left_case_fastening_v03_NOT_FOR_MANUFACTURE (Autodesk Fusion 360 design; units mm, degrees)
part number: 2026-11-07-02-20-21-225
part number: 2026-11-07-02-20-21-469
part number: 2026-11-07-02-20-24-646
part number: 2026-11-07-02-20-27-170
part number: 2026-11-07-02-26-06-783
Autodesk Fusion 360 part; units mm, degrees
sketch "スケッチ1" plane through (0, 0, 0) normal (0, 0, 1) x (1, 0, 0) in component "Lower_L_FROM_PCB_OUTLINE_PROVISIONAL"
  line L0 (-49.47, 7.054) -> (-65.52, 7.054) construction
  arc A0 (-65.52, 7.054) -> (-66.52, 6.054) centre (-65.52, 6.054) ccw construction
  line L1 (-66.52, 6.054) -> (-66.52, 3.354) construction
  arc A1 (-67.52, 2.354) -> (-66.52, 3.354) centre (-67.52, 3.354) ccw construction
  line L2 (-67.52, 2.354) -> (-84.57, 2.354) construction
  arc A2 (-84.57, 2.354) -> (-85.57, 1.354) centre (-84.57, 1.354) ccw construction
  line L3 (-85.57, 1.354) -> (-85.57, -3.646) construction
  arc A3 (-86.57, -4.646) -> (-85.57, -3.646) centre (-86.57, -3.646) ccw construction
  line L4 (-86.57, -4.646) -> (-103.62, -4.646) construction
  arc A4 (-103.62, -4.646) -> (-104.62, -5.646) centre (-103.6199, -5.6461) ccw construction
  line L5 (-104.62, -5.646) -> (-104.62, -78.846) construction
  arc A5 (-104.62, -78.846) -> (-103.62, -79.846) centre (-103.62, -78.846) ccw construction
  line L6 (-103.62, -79.846) -> (-87.57, -79.846) construction
  arc A6 (-87.57, -79.846) -> (-86.57, -78.846) centre (-87.57, -78.846) ccw construction
  line L7 (-86.57, -78.846) -> (-86.57, -73.846) construction
  arc A7 (-85.57, -72.846) -> (-86.57, -73.846) centre (-85.57, -73.846) ccw construction
  line L8 (-85.57, -72.846) -> (-68.52, -72.846) construction
  arc A8 (-68.52, -72.846) -> (-67.52, -71.846) centre (-68.52, -71.846) ccw construction
  line L9 (-67.52, -71.846) -> (-67.52, -69.146) construction
  arc A9 (-66.52, -68.146) -> (-67.52, -69.146) centre (-66.52, -69.146) ccw construction
  line L10 (-66.52, -68.146) -> (-49.47, -68.146) construction
  arc A10 (-49.47, -68.146) -> (-48.47, -67.146) centre (-49.47, -67.146) ccw construction
  line L11 (-48.47, -67.146) -> (-48.47, -55.096) construction
  arc A11 (-47.47, -54.096) -> (-48.47, -55.096) centre (-47.47, -55.096) ccw construction
  line L12 (-47.47, -54.096) -> (-44.47, -54.096) construction
  arc A12 (-43.47, -55.096) -> (-44.47, -54.096) centre (-44.47, -55.096) ccw construction
  line L13 (-43.47, -55.096) -> (-43.47, -76.846) construction
  arc A13 (-43.47, -76.846) -> (-42.47, -77.846) centre (-42.47, -76.846) ccw construction
  line L14 (-42.47, -77.846) -> (-25.5816, -77.846) construction
  arc A14 (-25.2605, -77.8719) -> (-25.5816, -77.846) centre (-25.5815, -79.8459) ccw construction
  line L15 (-25.2605, -77.8719) -> (-5.7378, -81.0467) construction
  arc A15 (-5.3997, -81.1324) -> (-5.7378, -81.0467) centre (-6.0588, -83.0207) ccw construction
  line L16 (-5.3997, -81.1324) -> (12.4958, -87.3783) construction
  arc A16 (12.4958, -87.3783) -> (13.765, -86.7762) centre (12.8253, -86.4342) ccw construction
  line L17 (13.765, -86.7762) -> (19.2592, -71.6805) construction
  arc A17 (19.2592, -71.6805) -> (18.6615, -70.3988) centre (18.3195, -71.3385) ccw construction
  line L18 (18.6615, -70.3988) -> (10.7342, -67.5136) construction
  arc A18 (10.0762, -66.5739) -> (10.7342, -67.5136) centre (11.0762, -66.5739) ccw construction
  line L19 (10.0762, -66.5739) -> (10.0762, -1.946) construction
  line L20 (10.0762, -1.946) -> (10.0762, -0.946) construction
  arc A19 (10.0762, -0.946) -> (9.0762, 0.054) centre (9.0762, -0.946) ccw construction
  line L21 (9.0762, 0.054) -> (-9.37, 0.054) construction
  arc A20 (-10.37, 1.054) -> (-9.37, 0.054) centre (-9.37, 1.054) ccw construction
  arc A21 (-10.37, 1.054) -> (-11.37, 2.054) centre (-11.37, 1.054) ccw construction
  line L22 (-11.37, 2.054) -> (-28.42, 2.054) construction
  arc A22 (-29.42, 3.054) -> (-28.42, 2.054) centre (-28.42, 3.054) ccw construction
  line L23 (-29.42, 3.054) -> (-29.42, 3.554) construction
  arc A23 (-29.42, 3.554) -> (-30.42, 4.554) centre (-30.42, 3.554) ccw construction
  line L24 (-30.42, 4.554) -> (-47.47, 4.554) construction
  arc A24 (-48.47, 5.554) -> (-47.47, 4.554) centre (-47.47, 5.554) ccw construction
  line L25 (-48.47, 5.554) -> (-48.47, 6.054) construction
  arc A25 (-48.47, 6.054) -> (-49.47, 7.054) centre (-49.47, 6.054) ccw construction
  line L26 (-49.47, 11.054) -> (-65.52, 11.054)
  arc A26 (-65.52, 11.054) -> (-70.511, 6.354) centre (-65.52, 6.054) ccw
  line L27 (-70.511, 6.354) -> (-84.57, 6.354)
  arc A27 (-84.57, 6.354) -> (-89.57, 1.354) centre (-84.57, 1.354) ccw
  line L28 (-89.57, 1.354) -> (-89.57, -0.646)
  line L29 (-89.57, -0.646) -> (-103.6201, -0.646)
  arc A28 (-103.6201, -0.646) -> (-108.62, -5.6459) centre (-103.6199, -5.6461) ccw
  line L30 (-108.62, -5.6459) -> (-108.62, -78.846)
  arc A29 (-108.62, -78.846) -> (-103.62, -83.846) centre (-103.62, -78.846) ccw
  line L31 (-103.62, -83.846) -> (-87.57, -83.846)
  arc A30 (-87.57, -83.846) -> (-82.57, -78.846) centre (-87.57, -78.846) ccw
  line L32 (-82.57, -78.846) -> (-82.57, -76.846)
  line L33 (-82.57, -76.846) -> (-68.52, -76.846)
  arc A31 (-68.52, -76.846) -> (-63.529, -72.146) centre (-68.52, -71.846) ccw
  line L34 (-63.529, -72.146) -> (-49.47, -72.146)
  arc A32 (-49.47, -72.146) -> (-47.47, -71.7286) centre (-49.47, -67.146) ccw
  line L35 (-47.47, -71.7286) -> (-47.47, -76.846)
  arc A33 (-47.47, -76.846) -> (-42.47, -81.846) centre (-42.47, -76.846) ccw
  line L36 (-42.47, -81.846) -> (-25.7431, -81.846)
  line L37 (-25.7431, -81.846) -> (-6.5526, -84.9667)
  line L38 (-6.5526, -84.9667) -> (11.1777, -91.1549)
  arc A34 (11.1777, -91.1549) -> (17.5238, -88.1442) centre (12.8253, -86.4342) ccw
  line L39 (17.5238, -88.1442) -> (23.0179, -73.0485)
  arc A35 (23.0179, -73.0485) -> (20.0295, -66.64) centre (18.3195, -71.3385) ccw
  line L40 (20.0295, -66.64) -> (14.0762, -64.4733)
  line L41 (14.0762, -64.4733) -> (14.0762, -1.946)
  line L42 (14.0762, -1.946) -> (14.0762, -0.946)
  arc A36 (14.0762, -0.946) -> (9.0762, 4.054) centre (9.0762, -0.946) ccw
  line L43 (9.0762, 4.054) -> (-7.37, 4.054)
  arc A37 (-7.37, 4.054) -> (-11.37, 6.054) centre (-11.37, 1.054) ccw
  line L44 (-11.37, 6.054) -> (-26.0899, 6.054)
  arc A38 (-26.0899, 6.054) -> (-30.42, 8.554) centre (-30.42, 3.554) ccw
  line L45 (-30.42, 8.554) -> (-45.1399, 8.554)
  arc A39 (-45.1399, 8.554) -> (-49.47, 11.054) centre (-49.47, 6.054) ccw
  dimension "d13" = 4
extrude "Continuous_bottom_floor_2mm" add sketch "スケッチ1" along normal blind 2 makes body 1 in component "Lower_L_FROM_PCB_OUTLINE_PROVISIONAL"
ref_plane "作業平面1" through (0, 0, 2) normal (0, 0, 1) x (1, 0, 0) in component "Lower_L_FROM_PCB_OUTLINE_PROVISIONAL"
sketch "スケッチ2" plane through (0, 0, 2) normal (0, 0, 1) x (1, 0, 0) in component "Lower_L_FROM_PCB_OUTLINE_PROVISIONAL"
  line L0 (-49.47, 7.054) -> (-65.52, 7.054) construction
  arc A0 (-65.52, 7.054) -> (-66.52, 6.054) centre (-65.52, 6.054) ccw construction
  line L1 (-66.52, 6.054) -> (-66.52, 3.354) construction
  arc A1 (-67.52, 2.354) -> (-66.52, 3.354) centre (-67.52, 3.354) ccw construction
  line L2 (-67.52, 2.354) -> (-84.57, 2.354) construction
  arc A2 (-84.57, 2.354) -> (-85.57, 1.354) centre (-84.57, 1.354) ccw construction
  line L3 (-85.57, 1.354) -> (-85.57, -3.646) construction
  arc A3 (-86.57, -4.646) -> (-85.57, -3.646) centre (-86.57, -3.646) ccw construction
  line L4 (-86.57, -4.646) -> (-103.62, -4.646) construction
  arc A4 (-103.62, -4.646) -> (-104.62, -5.646) centre (-103.6199, -5.6461) ccw construction
  line L5 (-104.62, -5.646) -> (-104.62, -78.846) construction
  arc A5 (-104.62, -78.846) -> (-103.62, -79.846) centre (-103.62, -78.846) ccw construction
  line L6 (-103.62, -79.846) -> (-87.57, -79.846) construction
  arc A6 (-87.57, -79.846) -> (-86.57, -78.846) centre (-87.57, -78.846) ccw construction
  line L7 (-86.57, -78.846) -> (-86.57, -73.846) construction
  arc A7 (-85.57, -72.846) -> (-86.57, -73.846) centre (-85.57, -73.846) ccw construction
  line L8 (-85.57, -72.846) -> (-68.52, -72.846) construction
  arc A8 (-68.52, -72.846) -> (-67.52, -71.846) centre (-68.52, -71.846) ccw construction
  line L9 (-67.52, -71.846) -> (-67.52, -69.146) construction
  arc A9 (-66.52, -68.146) -> (-67.52, -69.146) centre (-66.52, -69.146) ccw construction
  line L10 (-66.52, -68.146) -> (-49.47, -68.146) construction
  arc A10 (-49.47, -68.146) -> (-48.47, -67.146) centre (-49.47, -67.146) ccw construction
  line L11 (-48.47, -67.146) -> (-48.47, -55.096) construction
  arc A11 (-47.47, -54.096) -> (-48.47, -55.096) centre (-47.47, -55.096) ccw construction
  line L12 (-47.47, -54.096) -> (-44.47, -54.096) construction
  arc A12 (-43.47, -55.096) -> (-44.47, -54.096) centre (-44.47, -55.096) ccw construction
  line L13 (-43.47, -55.096) -> (-43.47, -76.846) construction
  arc A13 (-43.47, -76.846) -> (-42.47, -77.846) centre (-42.47, -76.846) ccw construction
  line L14 (-42.47, -77.846) -> (-25.5816, -77.846) construction
  arc A14 (-25.2605, -77.8719) -> (-25.5816, -77.846) centre (-25.5815, -79.8459) ccw construction
  line L15 (-25.2605, -77.8719) -> (-5.7378, -81.0467) construction
  arc A15 (-5.3997, -81.1324) -> (-5.7378, -81.0467) centre (-6.0588, -83.0207) ccw construction
  line L16 (-5.3997, -81.1324) -> (12.4958, -87.3783) construction
  arc A16 (12.4958, -87.3783) -> (13.765, -86.7762) centre (12.8253, -86.4342) ccw construction
  line L17 (13.765, -86.7762) -> (19.2592, -71.6805) construction
  arc A17 (19.2592, -71.6805) -> (18.6615, -70.3988) centre (18.3195, -71.3385) ccw construction
  line L18 (18.6615, -70.3988) -> (10.7342, -67.5136) construction
  arc A18 (10.0762, -66.5739) -> (10.7342, -67.5136) centre (11.0762, -66.5739) ccw construction
  line L19 (10.0762, -66.5739) -> (10.0762, -1.946) construction
  line L20 (10.0762, -1.946) -> (10.0762, -0.946) construction
  arc A19 (10.0762, -0.946) -> (9.0762, 0.054) centre (9.0762, -0.946) ccw construction
  line L21 (9.0762, 0.054) -> (-9.37, 0.054) construction
  arc A20 (-10.37, 1.054) -> (-9.37, 0.054) centre (-9.37, 1.054) ccw construction
  arc A21 (-10.37, 1.054) -> (-11.37, 2.054) centre (-11.37, 1.054) ccw construction
  line L22 (-11.37, 2.054) -> (-28.42, 2.054) construction
  arc A22 (-29.42, 3.054) -> (-28.42, 2.054) centre (-28.42, 3.054) ccw construction
  line L23 (-29.42, 3.054) -> (-29.42, 3.554) construction
  arc A23 (-29.42, 3.554) -> (-30.42, 4.554) centre (-30.42, 3.554) ccw construction
  line L24 (-30.42, 4.554) -> (-47.47, 4.554) construction
  arc A24 (-48.47, 5.554) -> (-47.47, 4.554) centre (-47.47, 5.554) ccw construction
  line L25 (-48.47, 5.554) -> (-48.47, 6.054) construction
  arc A25 (-48.47, 6.054) -> (-49.47, 7.054) centre (-49.47, 6.054) ccw construction
  line L26 (-49.47, 11.054) -> (-65.52, 11.054)
  arc A26 (-65.52, 11.054) -> (-70.511, 6.354) centre (-65.52, 6.054) ccw
  line L27 (-70.511, 6.354) -> (-84.57, 6.354)
  arc A27 (-84.57, 6.354) -> (-89.57, 1.354) centre (-84.57, 1.354) ccw
  line L28 (-89.57, 1.354) -> (-89.57, -0.646)
  line L29 (-89.57, -0.646) -> (-103.6201, -0.646)
  arc A28 (-103.6201, -0.646) -> (-108.62, -5.6459) centre (-103.6199, -5.6461) ccw
  line L30 (-108.62, -5.6459) -> (-108.62, -78.846)
  arc A29 (-108.62, -78.846) -> (-103.62, -83.846) centre (-103.62, -78.846) ccw
  line L31 (-103.62, -83.846) -> (-87.57, -83.846)
  arc A30 (-87.57, -83.846) -> (-82.57, -78.846) centre (-87.57, -78.846) ccw
  line L32 (-82.57, -78.846) -> (-82.57, -76.846)
  line L33 (-82.57, -76.846) -> (-68.52, -76.846)
  arc A31 (-68.52, -76.846) -> (-63.529, -72.146) centre (-68.52, -71.846) ccw
  line L34 (-63.529, -72.146) -> (-49.47, -72.146)
  arc A32 (-49.47, -72.146) -> (-47.47, -71.7286) centre (-49.47, -67.146) ccw
  line L35 (-47.47, -71.7286) -> (-47.47, -76.846)
  arc A33 (-47.47, -76.846) -> (-42.47, -81.846) centre (-42.47, -76.846) ccw
  line L36 (-42.47, -81.846) -> (-25.7431, -81.846)
  line L37 (-25.7431, -81.846) -> (-6.5526, -84.9667)
  line L38 (-6.5526, -84.9667) -> (11.1777, -91.1549)
  arc A34 (11.1777, -91.1549) -> (17.5238, -88.1442) centre (12.8253, -86.4342) ccw
  line L39 (17.5238, -88.1442) -> (23.0179, -73.0485)
  arc A35 (23.0179, -73.0485) -> (20.0295, -66.64) centre (18.3195, -71.3385) ccw
  line L40 (20.0295, -66.64) -> (14.0762, -64.4733)
  line L41 (14.0762, -64.4733) -> (14.0762, -1.946)
  line L42 (14.0762, -1.946) -> (14.0762, -0.946)
  arc A36 (14.0762, -0.946) -> (9.0762, 4.054) centre (9.0762, -0.946) ccw
  line L43 (9.0762, 4.054) -> (-7.37, 4.054)
  arc A37 (-7.37, 4.054) -> (-11.37, 6.054) centre (-11.37, 1.054) ccw
  line L44 (-11.37, 6.054) -> (-26.0899, 6.054)
  arc A38 (-26.0899, 6.054) -> (-30.42, 8.554) centre (-30.42, 3.554) ccw
  line L45 (-30.42, 8.554) -> (-45.1399, 8.554)
  arc A39 (-45.1399, 8.554) -> (-49.47, 11.054) centre (-49.47, 6.054) ccw
  line L46 (-49.47, 8.054) -> (-65.52, 8.054)
  arc A40 (-65.52, 8.054) -> (-67.52, 6.054) centre (-65.52, 6.054) ccw
  line L47 (-67.52, 6.054) -> (-67.52, 3.354)
  line L48 (-67.52, 3.354) -> (-84.57, 3.354)
  arc A41 (-84.57, 3.354) -> (-86.57, 1.354) centre (-84.57, 1.354) ccw
  line L49 (-86.57, 1.354) -> (-86.57, -3.646)
  line L50 (-86.57, -3.646) -> (-103.62, -3.646)
  arc A42 (-103.62, -3.646) -> (-105.62, -5.646) centre (-103.6199, -5.6461) ccw
  line L51 (-105.62, -5.646) -> (-105.62, -78.846)
  arc A43 (-105.62, -78.846) -> (-103.62, -80.846) centre (-103.62, -78.846) ccw
  line L52 (-103.62, -80.846) -> (-87.57, -80.846)
  arc A44 (-87.57, -80.846) -> (-85.57, -78.846) centre (-87.57, -78.846) ccw
  line L53 (-85.57, -78.846) -> (-85.57, -73.846)
  line L54 (-85.57, -73.846) -> (-68.52, -73.846)
  arc A45 (-68.52, -73.846) -> (-66.52, -71.846) centre (-68.52, -71.846) ccw
  line L55 (-66.52, -71.846) -> (-66.52, -69.146)
  line L56 (-66.52, -69.146) -> (-49.47, -69.146)
  arc A46 (-49.47, -69.146) -> (-47.47, -67.146) centre (-49.47, -67.146) ccw
  line L57 (-47.47, -67.146) -> (-47.47, -55.096)
  line L58 (-47.47, -55.096) -> (-44.47, -55.096)
  line L59 (-44.47, -55.096) -> (-44.47, -76.846)
  arc A47 (-44.47, -76.846) -> (-42.47, -78.846) centre (-42.47, -76.846) ccw
  line L60 (-42.47, -78.846) -> (-25.5816, -78.846)
  arc A48 (-25.4211, -78.859) -> (-25.5816, -78.846) centre (-25.5815, -79.8459) ccw
  line L61 (-25.4211, -78.859) -> (-5.8983, -82.0337)
  arc A49 (-5.7293, -82.0766) -> (-5.8983, -82.0337) centre (-6.0588, -83.0207) ccw
  line L62 (-5.7293, -82.0766) -> (12.1663, -88.3225)
  arc A50 (12.1663, -88.3225) -> (14.7047, -87.1182) centre (12.8253, -86.4342) ccw
  line L63 (14.7047, -87.1182) -> (20.1989, -72.0225)
  arc A51 (20.1989, -72.0225) -> (19.0035, -69.4591) centre (18.3195, -71.3385) ccw
  line L64 (19.0035, -69.4591) -> (11.0762, -66.5739)
  line L65 (11.0762, -66.5739) -> (11.0762, -1.946)
  line L66 (11.0762, -1.946) -> (11.0762, -0.946)
  arc A52 (11.0762, -0.946) -> (9.0762, 1.054) centre (9.0762, -0.946) ccw
  line L67 (9.0762, 1.054) -> (-9.37, 1.054)
  arc A53 (-9.37, 1.054) -> (-11.37, 3.054) centre (-11.37, 1.054) ccw
  line L68 (-11.37, 3.054) -> (-28.42, 3.054)
  line L69 (-28.42, 3.054) -> (-28.42, 3.554)
  arc A54 (-28.42, 3.554) -> (-30.42, 5.554) centre (-30.42, 3.554) ccw
  line L70 (-30.42, 5.554) -> (-47.47, 5.554)
  line L71 (-47.47, 5.554) -> (-47.47, 6.054)
  arc A55 (-47.47, 6.054) -> (-49.47, 8.054) centre (-49.47, 6.054) ccw
  dimension "d18" = 4
  dimension "d19" = 1
extrude "Perimeter_wall_nominal_3mm" add sketch "スケッチ2" along normal blind 8.5 bodies 1 in component "Lower_L_FROM_PCB_OUTLINE_PROVISIONAL"
sketch "スケッチ3" plane through (0, 0, 2) normal (0, 0, 1) x (1, 0, 0) in component "Lower_L_FROM_PCB_OUTLINE_PROVISIONAL"
  line L0 (-106.62, -67) -> (-86.5, -67)
  line L1 (-86.5, -67) -> (-86.5, -6.2)
  line L2 (-86.5, -6.2) -> (-106.62, -6.2)
  line L3 (-106.62, -6.2) -> (-106.62, -67)
extrude "Raised_stand_backing_connected_to_wall" add sketch "スケッチ3" along normal blind 3.7 bodies 1 in component "Lower_L_FROM_PCB_OUTLINE_PROVISIONAL"
sketch "スケッチ4" plane through (0, 0, 0) normal (0, 0, 1) x (1, 0, 0) in component "Lower_L_FROM_PCB_OUTLINE_PROVISIONAL"
  line L0 (-101.1, -65) -> (-90.7, -65)
  line L1 (-88.5, -62.8) -> (-88.5, -10.4)
  line L2 (-90.7, -8.2) -> (-101.1, -8.2)
  line L3 (-103.3, -10.4) -> (-103.3, -62.8)
  arc A0 (-90.7, -65) -> (-88.5, -62.8) centre (-90.7, -62.8) ccw
  arc A1 (-88.5, -10.4) -> (-90.7, -8.2) centre (-90.7, -10.4) ccw
  arc A2 (-101.1, -8.2) -> (-103.3, -10.4) centre (-101.1, -10.4) ccw
  arc A3 (-103.3, -62.8) -> (-101.1, -65) centre (-101.1, -62.8) ccw
extrude "Stand_pocket_56p8x14p8_R2p2" cut sketch "スケッチ4" along normal blind 3.7 bodies 1 in component "Lower_L_FROM_PCB_OUTLINE_PROVISIONAL"
ref_plane "作業平面2" through (0, 0, 8) normal (0, 0, 1) x (1, 0, 0) in component "Lower_L_FROM_PCB_OUTLINE_PROVISIONAL"
sketch "スケッチ5" plane through (0, 0, 8) normal (0, 0, 1) x (1, 0, 0) in component "Lower_L_FROM_PCB_OUTLINE_PROVISIONAL"
  line L0 (-106.12, -61) -> (-103.82, -61)
  line L1 (-103.82, -61) -> (-103.82, -53)
  line L2 (-103.82, -53) -> (-106.12, -53)
  line L3 (-106.12, -53) -> (-106.12, -61)
extrude "PCB_edge_support_1_INSULATION_PENDING" add sketch "スケッチ5" along normal blind 3.3 bodies 1 in component "Lower_L_FROM_PCB_OUTLINE_PROVISIONAL"
sketch "スケッチ6" plane through (0, 0, 8) normal (0, 0, 1) x (1, 0, 0) in component "Lower_L_FROM_PCB_OUTLINE_PROVISIONAL"
  line L0 (-106.12, -27) -> (-103.82, -27)
  line L1 (-103.82, -27) -> (-103.82, -19)
  line L2 (-103.82, -19) -> (-106.12, -19)
  line L3 (-106.12, -19) -> (-106.12, -27)
extrude "PCB_edge_support_2_INSULATION_PENDING" add sketch "スケッチ6" along normal blind 3.3 bodies 1 in component "Lower_L_FROM_PCB_OUTLINE_PROVISIONAL"
sketch "スケッチ7" plane through (0, 0, 8) normal (0, 0, 1) x (1, 0, 0) in component "Lower_L_FROM_PCB_OUTLINE_PROVISIONAL"
  line L0 (9.2762, -43) -> (11.5762, -43)
  line L1 (11.5762, -43) -> (11.5762, -37)
  line L2 (11.5762, -37) -> (9.2762, -37)
  line L3 (9.2762, -37) -> (9.2762, -43)
extrude "PCB_edge_support_3_INSULATION_PENDING" add sketch "スケッチ7" along normal blind 3.3 bodies 1 in component "Lower_L_FROM_PCB_OUTLINE_PROVISIONAL"
sketch "スケッチ8" plane through (0, 0, 8) normal (0, 0, 1) x (1, 0, 0) in component "Lower_L_FROM_PCB_OUTLINE_PROVISIONAL"
  line L0 (-60, 6.254) -> (-54, 6.254)
  line L1 (-54, 6.254) -> (-54, 8.554)
  line L2 (-54, 8.554) -> (-60, 8.554)
  line L3 (-60, 8.554) -> (-60, 6.254)
extrude "PCB_edge_support_4_INSULATION_PENDING" add sketch "スケッチ8" along normal blind 3.3 bodies 1 in component "Lower_L_FROM_PCB_OUTLINE_PROVISIONAL"
sketch "スケッチ1 (2)" plane through (0, 0, 0) normal (0, 0, 1) x (1, 0, 0) in component "Upper_L_PERIMETER_ONLY_NO_SWITCH_PLATE"
  line L0 (-49.47, 7.054) -> (-65.52, 7.054) construction
  arc A0 (-65.52, 7.054) -> (-66.52, 6.054) centre (-65.52, 6.054) ccw construction
  line L1 (-66.52, 6.054) -> (-66.52, 3.354) construction
  arc A1 (-67.52, 2.354) -> (-66.52, 3.354) centre (-67.52, 3.354) ccw construction
  line L2 (-67.52, 2.354) -> (-84.57, 2.354) construction
  arc A2 (-84.57, 2.354) -> (-85.57, 1.354) centre (-84.57, 1.354) ccw construction
  line L3 (-85.57, 1.354) -> (-85.57, -3.646) construction
  arc A3 (-86.57, -4.646) -> (-85.57, -3.646) centre (-86.57, -3.646) ccw construction
  line L4 (-86.57, -4.646) -> (-103.62, -4.646) construction
  arc A4 (-103.62, -4.646) -> (-104.62, -5.646) centre (-103.6199, -5.6461) ccw construction
  line L5 (-104.62, -5.646) -> (-104.62, -78.846) construction
  arc A5 (-104.62, -78.846) -> (-103.62, -79.846) centre (-103.62, -78.846) ccw construction
  line L6 (-103.62, -79.846) -> (-87.57, -79.846) construction
  arc A6 (-87.57, -79.846) -> (-86.57, -78.846) centre (-87.57, -78.846) ccw construction
  line L7 (-86.57, -78.846) -> (-86.57, -73.846) construction
  arc A7 (-85.57, -72.846) -> (-86.57, -73.846) centre (-85.57, -73.846) ccw construction
  line L8 (-85.57, -72.846) -> (-68.52, -72.846) construction
  arc A8 (-68.52, -72.846) -> (-67.52, -71.846) centre (-68.52, -71.846) ccw construction
  line L9 (-67.52, -71.846) -> (-67.52, -69.146) construction
  arc A9 (-66.52, -68.146) -> (-67.52, -69.146) centre (-66.52, -69.146) ccw construction
  line L10 (-66.52, -68.146) -> (-49.47, -68.146) construction
  arc A10 (-49.47, -68.146) -> (-48.47, -67.146) centre (-49.47, -67.146) ccw construction
  line L11 (-48.47, -67.146) -> (-48.47, -55.096) construction
  arc A11 (-47.47, -54.096) -> (-48.47, -55.096) centre (-47.47, -55.096) ccw construction
  line L12 (-47.47, -54.096) -> (-44.47, -54.096) construction
  arc A12 (-43.47, -55.096) -> (-44.47, -54.096) centre (-44.47, -55.096) ccw construction
  line L13 (-43.47, -55.096) -> (-43.47, -76.846) construction
  arc A13 (-43.47, -76.846) -> (-42.47, -77.846) centre (-42.47, -76.846) ccw construction
  line L14 (-42.47, -77.846) -> (-25.5816, -77.846) construction
  arc A14 (-25.2605, -77.8719) -> (-25.5816, -77.846) centre (-25.5815, -79.8459) ccw construction
  line L15 (-25.2605, -77.8719) -> (-5.7378, -81.0467) construction
  arc A15 (-5.3997, -81.1324) -> (-5.7378, -81.0467) centre (-6.0588, -83.0207) ccw construction
  line L16 (-5.3997, -81.1324) -> (12.4958, -87.3783) construction
  arc A16 (12.4958, -87.3783) -> (13.765, -86.7762) centre (12.8253, -86.4342) ccw construction
  line L17 (13.765, -86.7762) -> (19.2592, -71.6805) construction
  arc A17 (19.2592, -71.6805) -> (18.6615, -70.3988) centre (18.3195, -71.3385) ccw construction
  line L18 (18.6615, -70.3988) -> (10.7342, -67.5136) construction
  arc A18 (10.0762, -66.5739) -> (10.7342, -67.5136) centre (11.0762, -66.5739) ccw construction
  line L19 (10.0762, -66.5739) -> (10.0762, -1.946) construction
  line L20 (10.0762, -1.946) -> (10.0762, -0.946) construction
  arc A19 (10.0762, -0.946) -> (9.0762, 0.054) centre (9.0762, -0.946) ccw construction
  line L21 (9.0762, 0.054) -> (-9.37, 0.054) construction
  arc A20 (-10.37, 1.054) -> (-9.37, 0.054) centre (-9.37, 1.054) ccw construction
  arc A21 (-10.37, 1.054) -> (-11.37, 2.054) centre (-11.37, 1.054) ccw construction
  line L22 (-11.37, 2.054) -> (-28.42, 2.054) construction
  arc A22 (-29.42, 3.054) -> (-28.42, 2.054) centre (-28.42, 3.054) ccw construction
  line L23 (-29.42, 3.054) -> (-29.42, 3.554) construction
  arc A23 (-29.42, 3.554) -> (-30.42, 4.554) centre (-30.42, 3.554) ccw construction
  line L24 (-30.42, 4.554) -> (-47.47, 4.554) construction
  arc A24 (-48.47, 5.554) -> (-47.47, 4.554) centre (-47.47, 5.554) ccw construction
  line L25 (-48.47, 5.554) -> (-48.47, 6.054) construction
  arc A25 (-48.47, 6.054) -> (-49.47, 7.054) centre (-49.47, 6.054) ccw construction
  line L26 (-49.47, 11.054) -> (-65.52, 11.054)
  arc A26 (-65.52, 11.054) -> (-70.511, 6.354) centre (-65.52, 6.054) ccw
  line L27 (-70.511, 6.354) -> (-84.57, 6.354)
  arc A27 (-84.57, 6.354) -> (-89.57, 1.354) centre (-84.57, 1.354) ccw
  line L28 (-89.57, 1.354) -> (-89.57, -0.646)
  line L29 (-89.57, -0.646) -> (-103.6201, -0.646)
  arc A28 (-103.6201, -0.646) -> (-108.62, -5.6459) centre (-103.6199, -5.6461) ccw
  line L30 (-108.62, -5.6459) -> (-108.62, -78.846)
  arc A29 (-108.62, -78.846) -> (-103.62, -83.846) centre (-103.62, -78.846) ccw
  line L31 (-103.62, -83.846) -> (-87.57, -83.846)
  arc A30 (-87.57, -83.846) -> (-82.57, -78.846) centre (-87.57, -78.846) ccw
  line L32 (-82.57, -78.846) -> (-82.57, -76.846)
  line L33 (-82.57, -76.846) -> (-68.52, -76.846)
  arc A31 (-68.52, -76.846) -> (-63.529, -72.146) centre (-68.52, -71.846) ccw
  line L34 (-63.529, -72.146) -> (-49.47, -72.146)
  arc A32 (-49.47, -72.146) -> (-47.47, -71.7286) centre (-49.47, -67.146) ccw
  line L35 (-47.47, -71.7286) -> (-47.47, -76.846)
  arc A33 (-47.47, -76.846) -> (-42.47, -81.846) centre (-42.47, -76.846) ccw
  line L36 (-42.47, -81.846) -> (-25.7431, -81.846)
  line L37 (-25.7431, -81.846) -> (-6.5526, -84.9667)
  line L38 (-6.5526, -84.9667) -> (11.1777, -91.1549)
  arc A34 (11.1777, -91.1549) -> (17.5238, -88.1442) centre (12.8253, -86.4342) ccw
  line L39 (17.5238, -88.1442) -> (23.0179, -73.0485)
  arc A35 (23.0179, -73.0485) -> (20.0295, -66.64) centre (18.3195, -71.3385) ccw
  line L40 (20.0295, -66.64) -> (14.0762, -64.4733)
  line L41 (14.0762, -64.4733) -> (14.0762, -1.946)
  line L42 (14.0762, -1.946) -> (14.0762, -0.946)
  arc A36 (14.0762, -0.946) -> (9.0762, 4.054) centre (9.0762, -0.946) ccw
  line L43 (9.0762, 4.054) -> (-7.37, 4.054)
  arc A37 (-7.37, 4.054) -> (-11.37, 6.054) centre (-11.37, 1.054) ccw
  line L44 (-11.37, 6.054) -> (-26.0899, 6.054)
  arc A38 (-26.0899, 6.054) -> (-30.42, 8.554) centre (-30.42, 3.554) ccw
  line L45 (-30.42, 8.554) -> (-45.1399, 8.554)
  arc A39 (-45.1399, 8.554) -> (-49.47, 11.054) centre (-49.47, 6.054) ccw
  line L46 (-49.47, 8.054) -> (-65.52, 8.054)
  arc A40 (-65.52, 8.054) -> (-67.52, 6.054) centre (-65.52, 6.054) ccw
  line L47 (-67.52, 6.054) -> (-67.52, 3.354)
  line L48 (-67.52, 3.354) -> (-84.57, 3.354)
  arc A41 (-84.57, 3.354) -> (-86.57, 1.354) centre (-84.57, 1.354) ccw
  line L49 (-86.57, 1.354) -> (-86.57, -3.646)
  line L50 (-86.57, -3.646) -> (-103.62, -3.646)
  arc A42 (-103.62, -3.646) -> (-105.62, -5.646) centre (-103.6199, -5.6461) ccw
  line L51 (-105.62, -5.646) -> (-105.62, -78.846)
  arc A43 (-105.62, -78.846) -> (-103.62, -80.846) centre (-103.62, -78.846) ccw
  line L52 (-103.62, -80.846) -> (-87.57, -80.846)
  arc A44 (-87.57, -80.846) -> (-85.57, -78.846) centre (-87.57, -78.846) ccw
  line L53 (-85.57, -78.846) -> (-85.57, -73.846)
  line L54 (-85.57, -73.846) -> (-68.52, -73.846)
  arc A45 (-68.52, -73.846) -> (-66.52, -71.846) centre (-68.52, -71.846) ccw
  line L55 (-66.52, -71.846) -> (-66.52, -69.146)
  line L56 (-66.52, -69.146) -> (-49.47, -69.146)
  arc A46 (-49.47, -69.146) -> (-47.47, -67.146) centre (-49.47, -67.146) ccw
  line L57 (-47.47, -67.146) -> (-47.47, -55.096)
  line L58 (-47.47, -55.096) -> (-44.47, -55.096)
  line L59 (-44.47, -55.096) -> (-44.47, -76.846)
  arc A47 (-44.47, -76.846) -> (-42.47, -78.846) centre (-42.47, -76.846) ccw
  line L60 (-42.47, -78.846) -> (-25.5816, -78.846)
  arc A48 (-25.4211, -78.859) -> (-25.5816, -78.846) centre (-25.5815, -79.8459) ccw
  line L61 (-25.4211, -78.859) -> (-5.8983, -82.0337)
  arc A49 (-5.7293, -82.0766) -> (-5.8983, -82.0337) centre (-6.0588, -83.0207) ccw
  line L62 (-5.7293, -82.0766) -> (12.1663, -88.3225)
  arc A50 (12.1663, -88.3225) -> (14.7047, -87.1182) centre (12.8253, -86.4342) ccw
  line L63 (14.7047, -87.1182) -> (20.1989, -72.0225)
  arc A51 (20.1989, -72.0225) -> (19.0035, -69.4591) centre (18.3195, -71.3385) ccw
  line L64 (19.0035, -69.4591) -> (11.0762, -66.5739)
  line L65 (11.0762, -66.5739) -> (11.0762, -1.946)
  line L66 (11.0762, -1.946) -> (11.0762, -0.946)
  arc A52 (11.0762, -0.946) -> (9.0762, 1.054) centre (9.0762, -0.946) ccw
  line L67 (9.0762, 1.054) -> (-9.37, 1.054)
  arc A53 (-9.37, 1.054) -> (-11.37, 3.054) centre (-11.37, 1.054) ccw
  line L68 (-11.37, 3.054) -> (-28.42, 3.054)
  line L69 (-28.42, 3.054) -> (-28.42, 3.554)
  arc A54 (-28.42, 3.554) -> (-30.42, 5.554) centre (-30.42, 3.554) ccw
  line L70 (-30.42, 5.554) -> (-47.47, 5.554)
  line L71 (-47.47, 5.554) -> (-47.47, 6.054)
  arc A55 (-47.47, 6.054) -> (-49.47, 8.054) centre (-49.47, 6.054) ccw
  dimension "d36" = 4
  dimension "d37" = 1
extrude "Provisional_upper_rim_NO_KEYCAP_HEIGHT_CERTIFICATION" add sketch "スケッチ1 (2)" along normal blind 5.5 separate body makes body 2 in component "Upper_L_PERIMETER_ONLY_NO_SWITCH_PLATE"
sketch "スケッチ9" plane through (0, 0, 0) normal (0, 0, 1) x (1, 0, 0) in component "Lower_L_FROM_PCB_OUTLINE_PROVISIONAL"
  circle A0 centre (-108.12, -59) radius 3
  circle A1 centre (-108.12, -17) radius 3
  circle A2 centre (13.5762, -59) radius 3
  circle A3 centre (13.5762, -17) radius 3
  dimension "d92" = 3
  dimension "d93" = 3
  dimension "d94" = 3
  dimension "d95" = 3
  measures "d92" radius of A0
  measures "d93" radius of A1
  measures "d94" radius of A2
  measures "d95" radius of A3
extrude "Four_external_M2_bosses" add sketch "スケッチ9" along normal blind 10.5 bodies 1 in component "Lower_L_FROM_PCB_OUTLINE_PROVISIONAL"
sketch "スケッチ2 (2)" plane through (0, 0, 0) normal (0, 0, 1) x (1, 0, 0) in component "Upper_L_PERIMETER_ONLY_NO_SWITCH_PLATE"
  circle A0 centre (-108.12, -59) radius 3
  circle A1 centre (-108.12, -17) radius 3
  circle A2 centre (13.5762, -59) radius 3
  circle A3 centre (13.5762, -17) radius 3
  dimension "d84" = 3
  dimension "d85" = 3
  dimension "d86" = 3
  dimension "d87" = 3
  measures "d84" radius of A0
  measures "d85" radius of A1
  measures "d86" radius of A2
  measures "d87" radius of A3
extrude "Four_external_M2_bosses'" add sketch "スケッチ2 (2)" along normal blind 5.5 bodies 2 in component "Upper_L_PERIMETER_ONLY_NO_SWITCH_PLATE"
sketch "スケッチ10" plane through (0, 0, 0) normal (0, 0, 1) x (1, 0, 0) in component "Lower_L_FROM_PCB_OUTLINE_PROVISIONAL"
  circle A0 centre (-108.12, -59) radius 1.1
  circle A1 centre (-108.12, -17) radius 1.1
  circle A2 centre (13.5762, -59) radius 1.1
  circle A3 centre (13.5762, -17) radius 1.1
  dimension "d96" = 1.1
  dimension "d97" = 1.1
  dimension "d98" = 1.1
  dimension "d99" = 1.1
  measures "d96" radius of A0
  measures "d97" radius of A1
  measures "d98" radius of A2
  measures "d99" radius of A3
extrude "M2_clearance_holes_NO_HEAD_SEATS" cut sketch "スケッチ10" along normal blind 10.5 bodies 1 in component "Lower_L_FROM_PCB_OUTLINE_PROVISIONAL"
sketch "スケッチ3 (2)" plane through (0, 0, 0) normal (0, 0, 1) x (1, 0, 0) in component "Upper_L_PERIMETER_ONLY_NO_SWITCH_PLATE"
  circle A0 centre (-108.12, -59) radius 0.8
  circle A1 centre (-108.12, -17) radius 0.8
  circle A2 centre (13.5762, -59) radius 0.8
  circle A3 centre (13.5762, -17) radius 0.8
  dimension "d88" = 0.8
  dimension "d89" = 0.8
  dimension "d90" = 0.8
  dimension "d91" = 0.8
  measures "d88" radius of A0
  measures "d89" radius of A1
  measures "d90" radius of A2
  measures "d91" radius of A3
extrude "M2_TAP_PILOTS_ONLY_THREAD_NOT_MODELED" cut sketch "スケッチ3 (2)" along normal blind 4.5 bodies 2 in component "Upper_L_PERIMETER_ONLY_NO_SWITCH_PLATE"
sketch "スケッチ1 (3)" plane through (0, 0, 0) normal (0, 0, 1) x (1, 0, 0) in component "PCB_L_v2_OUTLINE_REFERENCE_ACTUAL_REVISION_UNKNOWN"
  line L0 (-49.47, 7.054) -> (-65.52, 7.054)
  arc A0 (-65.52, 7.054) -> (-66.52, 6.054) centre (-65.52, 6.054) ccw
  line L1 (-66.52, 6.054) -> (-66.52, 3.354)
  arc A1 (-67.52, 2.354) -> (-66.52, 3.354) centre (-67.52, 3.354) ccw
  line L2 (-67.52, 2.354) -> (-84.57, 2.354)
  arc A2 (-84.57, 2.354) -> (-85.57, 1.354) centre (-84.57, 1.354) ccw
  line L3 (-85.57, 1.354) -> (-85.57, -3.646)
  arc A3 (-86.57, -4.646) -> (-85.57, -3.646) centre (-86.57, -3.646) ccw
  line L4 (-86.57, -4.646) -> (-103.62, -4.646)
  arc A4 (-103.62, -4.646) -> (-104.62, -5.646) centre (-103.6199, -5.6461) ccw
  line L5 (-104.62, -5.646) -> (-104.62, -78.846)
  arc A5 (-104.62, -78.846) -> (-103.62, -79.846) centre (-103.62, -78.846) ccw
  line L6 (-103.62, -79.846) -> (-87.57, -79.846)
  arc A6 (-87.57, -79.846) -> (-86.57, -78.846) centre (-87.57, -78.846) ccw
  line L7 (-86.57, -78.846) -> (-86.57, -73.846)
  arc A7 (-85.57, -72.846) -> (-86.57, -73.846) centre (-85.57, -73.846) ccw
  line L8 (-85.57, -72.846) -> (-68.52, -72.846)
  arc A8 (-68.52, -72.846) -> (-67.52, -71.846) centre (-68.52, -71.846) ccw
  line L9 (-67.52, -71.846) -> (-67.52, -69.146)
  arc A9 (-66.52, -68.146) -> (-67.52, -69.146) centre (-66.52, -69.146) ccw
  line L10 (-66.52, -68.146) -> (-49.47, -68.146)
  arc A10 (-49.47, -68.146) -> (-48.47, -67.146) centre (-49.47, -67.146) ccw
  line L11 (-48.47, -67.146) -> (-48.47, -55.096)
  arc A11 (-47.47, -54.096) -> (-48.47, -55.096) centre (-47.47, -55.096) ccw
  line L12 (-47.47, -54.096) -> (-44.47, -54.096)
  arc A12 (-43.47, -55.096) -> (-44.47, -54.096) centre (-44.47, -55.096) ccw
  line L13 (-43.47, -55.096) -> (-43.47, -76.846)
  arc A13 (-43.47, -76.846) -> (-42.47, -77.846) centre (-42.47, -76.846) ccw
  line L14 (-42.47, -77.846) -> (-25.5816, -77.846)
  arc A14 (-25.2605, -77.8719) -> (-25.5816, -77.846) centre (-25.5815, -79.8459) ccw
  line L15 (-25.2605, -77.8719) -> (-5.7378, -81.0467)
  arc A15 (-5.3997, -81.1324) -> (-5.7378, -81.0467) centre (-6.0588, -83.0207) ccw
  line L16 (-5.3997, -81.1324) -> (12.4958, -87.3783)
  arc A16 (12.4958, -87.3783) -> (13.765, -86.7762) centre (12.8253, -86.4342) ccw
  line L17 (13.765, -86.7762) -> (19.2592, -71.6805)
  arc A17 (19.2592, -71.6805) -> (18.6615, -70.3988) centre (18.3195, -71.3385) ccw
  line L18 (18.6615, -70.3988) -> (10.7342, -67.5136)
  arc A18 (10.0762, -66.5739) -> (10.7342, -67.5136) centre (11.0762, -66.5739) ccw
  line L19 (10.0762, -66.5739) -> (10.0762, -1.946)
  line L20 (10.0762, -1.946) -> (10.0762, -0.946)
  arc A19 (10.0762, -0.946) -> (9.0762, 0.054) centre (9.0762, -0.946) ccw
  line L21 (9.0762, 0.054) -> (-9.37, 0.054)
  arc A20 (-10.37, 1.054) -> (-9.37, 0.054) centre (-9.37, 1.054) ccw
  arc A21 (-10.37, 1.054) -> (-11.37, 2.054) centre (-11.37, 1.054) ccw
  line L22 (-11.37, 2.054) -> (-28.42, 2.054)
  arc A22 (-29.42, 3.054) -> (-28.42, 2.054) centre (-28.42, 3.054) ccw
  line L23 (-29.42, 3.054) -> (-29.42, 3.554)
  arc A23 (-29.42, 3.554) -> (-30.42, 4.554) centre (-30.42, 3.554) ccw
  line L24 (-30.42, 4.554) -> (-47.47, 4.554)
  arc A24 (-48.47, 5.554) -> (-47.47, 4.554) centre (-47.47, 5.554) ccw
  line L25 (-48.47, 5.554) -> (-48.47, 6.054)
  arc A25 (-48.47, 6.054) -> (-49.47, 7.054) centre (-49.47, 6.054) ccw
  circle A26 centre (-3.01, -75.606) radius 2.15
  circle A27 centre (-84.95, -54.286) radius 2.15
  circle A28 centre (-23.77, -71.026) radius 2.15
  circle A29 centre (-27.83, -35.536) radius 2.15
  circle A30 centre (-84.96, -16.186) radius 2.15
  circle A31 centre (5.5307, -63.001) radius 2.15
  circle A32 centre (-30, -13.986) radius 2.15
extrude "Public_PCB_reference_NOT_populated" add sketch "スケッチ1 (3)" along normal blind 1.6 separate body makes body 3 in component "PCB_L_v2_OUTLINE_REFERENCE_ACTUAL_REVISION_UNKNOWN"
sketch "スケッチ4 (2)" plane through (0, 0, 0) normal (0, 0, 1) x (1, 0, 0) in component "Upper_L_PERIMETER_ONLY_NO_SWITCH_PLATE"
  line L0 (-106.32, -61.2) -> (-103.62, -61.2)
  line L1 (-103.62, -61.2) -> (-103.62, -52.8)
  line L2 (-103.62, -52.8) -> (-106.32, -52.8)
  line L3 (-106.32, -52.8) -> (-106.32, -61.2)
extrude "Support_clearance_1_0p2mm" cut sketch "スケッチ4 (2)" along normal blind 1 sketch seen with x (1, 0, 0) y (0, 1, 0) z (0, 0, 1) at (0, 0, 10.5) bodies 1 in component "Lower_L_FROM_PCB_OUTLINE_PROVISIONAL"
extrude "押し出し4" cut sketch "スケッチ4 (2)" along normal blind 1 bodies 2 in component "Upper_L_PERIMETER_ONLY_NO_SWITCH_PLATE"
sketch "スケッチ5 (2)" plane through (0, 0, 0) normal (0, 0, 1) x (1, 0, 0) in component "Upper_L_PERIMETER_ONLY_NO_SWITCH_PLATE"
  line L0 (-106.32, -27.2) -> (-103.62, -27.2)
  line L1 (-103.62, -27.2) -> (-103.62, -18.8)
  line L2 (-103.62, -18.8) -> (-106.32, -18.8)
  line L3 (-106.32, -18.8) -> (-106.32, -27.2)
extrude "Support_clearance_2_0p2mm" cut sketch "スケッチ5 (2)" along normal blind 1 sketch seen with x (1, 0, 0) y (0, 1, 0) z (0, 0, 1) at (0, 0, 10.5) bodies 1 in component "Lower_L_FROM_PCB_OUTLINE_PROVISIONAL"
extrude "押し出し5" cut sketch "スケッチ5 (2)" along normal blind 1 bodies 2 in component "Upper_L_PERIMETER_ONLY_NO_SWITCH_PLATE"
sketch "スケッチ6 (2)" plane through (0, 0, 0) normal (0, 0, 1) x (1, 0, 0) in component "Upper_L_PERIMETER_ONLY_NO_SWITCH_PLATE"
  line L0 (9.0762, -43.2) -> (11.7762, -43.2)
  line L1 (11.7762, -43.2) -> (11.7762, -36.8)
  line L2 (11.7762, -36.8) -> (9.0762, -36.8)
  line L3 (9.0762, -36.8) -> (9.0762, -43.2)
extrude "Support_clearance_3_0p2mm" cut sketch "スケッチ6 (2)" along normal blind 1 sketch seen with x (1, 0, 0) y (0, 1, 0) z (0, 0, 1) at (0, 0, 10.5) bodies 1 in component "Lower_L_FROM_PCB_OUTLINE_PROVISIONAL"
extrude "押し出し6" cut sketch "スケッチ6 (2)" along normal blind 1 bodies 2 in component "Upper_L_PERIMETER_ONLY_NO_SWITCH_PLATE"
sketch "スケッチ7 (2)" plane through (0, 0, 0) normal (0, 0, 1) x (1, 0, 0) in component "Upper_L_PERIMETER_ONLY_NO_SWITCH_PLATE"
  line L0 (-60.2, 6.054) -> (-53.8, 6.054)
  line L1 (-53.8, 6.054) -> (-53.8, 8.754)
  line L2 (-53.8, 8.754) -> (-60.2, 8.754)
  line L3 (-60.2, 8.754) -> (-60.2, 6.054)
extrude "Support_clearance_4_0p2mm" cut sketch "スケッチ7 (2)" along normal blind 1 sketch seen with x (1, 0, 0) y (0, 1, 0) z (0, 0, 1) at (0, 0, 10.5) bodies 1 in component "Lower_L_FROM_PCB_OUTLINE_PROVISIONAL"
extrude "押し出し7" cut sketch "スケッチ7 (2)" along normal blind 1 bodies 2 in component "Upper_L_PERIMETER_ONLY_NO_SWITCH_PLATE"
sketch "スケッチ8 (2)" plane through (0, 0, 0) normal (0, 0, 1) x (1, 0, 0) in component "Upper_L_PERIMETER_ONLY_NO_SWITCH_PLATE"
  line L0 (-107.32, -62.2) -> (-102.62, -62.2)
  line L1 (-102.62, -62.2) -> (-102.62, -51.8)
  line L2 (-102.62, -51.8) -> (-107.32, -51.8)
  line L3 (-107.32, -51.8) -> (-107.32, -62.2)
extrude "Expanded_support_root_clearance_1" cut sketch "スケッチ8 (2)" along normal blind 1 bodies 2 in component "Upper_L_PERIMETER_ONLY_NO_SWITCH_PLATE"
sketch "スケッチ9 (2)" plane through (0, 0, 0) normal (0, 0, 1) x (1, 0, 0) in component "Upper_L_PERIMETER_ONLY_NO_SWITCH_PLATE"
  line L0 (-107.32, -28.2) -> (-102.62, -28.2)
  line L1 (-102.62, -28.2) -> (-102.62, -17.8)
  line L2 (-102.62, -17.8) -> (-107.32, -17.8)
  line L3 (-107.32, -17.8) -> (-107.32, -28.2)
extrude "Expanded_support_root_clearance_2" cut sketch "スケッチ9 (2)" along normal blind 1 bodies 2 in component "Upper_L_PERIMETER_ONLY_NO_SWITCH_PLATE"
sketch "スケッチ10 (2)" plane through (0, 0, 0) normal (0, 0, 1) x (1, 0, 0) in component "Upper_L_PERIMETER_ONLY_NO_SWITCH_PLATE"
  line L0 (8.0762, -44.2) -> (12.7762, -44.2)
  line L1 (12.7762, -44.2) -> (12.7762, -35.8)
  line L2 (12.7762, -35.8) -> (8.0762, -35.8)
  line L3 (8.0762, -35.8) -> (8.0762, -44.2)
extrude "Expanded_support_root_clearance_3" cut sketch "スケッチ10 (2)" along normal blind 1 bodies 2 in component "Upper_L_PERIMETER_ONLY_NO_SWITCH_PLATE"
sketch "スケッチ11" plane through (0, 0, 0) normal (0, 0, 1) x (1, 0, 0) in component "Upper_L_PERIMETER_ONLY_NO_SWITCH_PLATE"
  line L0 (-61.2, 5.054) -> (-52.8, 5.054)
  line L1 (-52.8, 5.054) -> (-52.8, 9.754)
  line L2 (-52.8, 9.754) -> (-61.2, 9.754)
  line L3 (-61.2, 9.754) -> (-61.2, 5.054)
extrude "Expanded_support_root_clearance_4" cut sketch "スケッチ11" along normal blind 1 bodies 2 in component "Upper_L_PERIMETER_ONLY_NO_SWITCH_PLATE"
fillet "Concave_vertical_corner_candidates_R1" radius 1 27 edges at (-60, 8.054, 9.25) (11.0762, -43, 9.25) (11.0762, -37, 9.25) (-105.62, -27, 9.25) (-105.62, -61, 9.25) (14.0762, -14.042, 5.25) (14.0762, -19.958, 5.25) (14.0762, -56.042, 5.25) (-108.62, -56.042, 5.25) (-108.62, -61.958, 5.25) (-105.62, -67, 3.85) (-105.62, -19, 9.25) (-105.62, -53, 9.25) (-108.62, -14.042, 5.25) (-108.62, -19.958, 5.25) (-105.62, -6.2, 3.85) (14.0762, -61.958, 5.25) (14.0762, -64.4733, 5.25) (-54, 8.054, 9.25) (-45.1399, 8.554, 5.25) (-26.0899, 6.054, 5.25) (-7.37, 4.054, 5.25) (-47.47, -71.7286, 5.25) (-63.529, -72.146, 5.25) (-82.57, -76.846, 5.25) (-89.57, -0.646, 5.25) (-70.511, 6.354, 5.25) on bodies 1 in component "Lower_L_FROM_PCB_OUTLINE_PROVISIONAL"
fillet "Concave_vertical_corner_candidates_R1'" radius 1 17 edges at (14.0762, -14.042, 2.75) (14.0762, -19.958, 2.75) (14.0762, -56.042, 2.75) (-108.62, -56.042, 2.75) (-108.62, -61.958, 2.75) (-108.62, -14.042, 2.75) (-108.62, -19.958, 2.75) (14.0762, -61.958, 2.75) (14.0762, -64.4733, 2.75) (-45.1399, 8.554, 2.75) (-26.0899, 6.054, 2.75) (-7.37, 4.054, 2.75) (-47.47, -71.7286, 2.75) (-63.529, -72.146, 2.75) (-82.57, -76.846, 2.75) (-89.57, -0.646, 2.75) (-70.511, 6.354, 2.75) on bodies 2 in component "Upper_L_PERIMETER_ONLY_NO_SWITCH_PLATE"
sketch "スケッチ1 (4)" plane through (0, 0, 0) normal (0, 0, 1) x (1, 0, 0) in component "Battery_L_INSTALLATION_ALLOWANCE_32x22x5p5_NOT_CELL"
  line L0 (0, 0) -> (32, 0)
  line L1 (32, 0) -> (32, 22)
  line L2 (32, 22) -> (0, 22)
  line L3 (0, 22) -> (0, 0)
extrude "押し出し1" add sketch "スケッチ1 (4)" along normal blind 5.5 separate body makes body 4 in component "Battery_L_INSTALLATION_ALLOWANCE_32x22x5p5_NOT_CELL"
sketch "スケッチ11 (2)" plane through (0, 0, 0) normal (0, 0, 1) x (1, 0, 0) in component "Lower_L_FROM_PCB_OUTLINE_PROVISIONAL"
  circle A0 centre (-108.12, -59) radius 2.1
  circle A1 centre (-108.12, -17) radius 2.1
  circle A2 centre (13.5762, -59) radius 2.1
  circle A3 centre (13.5762, -17) radius 2.1
  dimension "d100" = 2.1
  dimension "d101" = 2.1
  dimension "d102" = 2.1
  dimension "d103" = 2.1
  measures "d100" radius of A0
  measures "d101" radius of A1
  measures "d102" radius of A2
  measures "d103" radius of A3
extrude "Four_D4p2_head_seats_depth_2p2" cut sketch "スケッチ11 (2)" along normal blind 2.2 bodies 1 in component "Lower_L_FROM_PCB_OUTLINE_PROVISIONAL"
component "Lower_L_FROM_PCB_OUTLINE_PROVISIONAL" placed x (1, 0, 0) y (0, 1, 0) z (0, 0, 1) at (0, 0, -11.5)
component "Upper_L_PERIMETER_ONLY_NO_SWITCH_PLATE" placed x (1, 0, 0) y (0, 1, 0) z (0, 0, 1) at (0, 0, -1)
component "PCB_L_v2_OUTLINE_REFERENCE_ACTUAL_REVISION_UNKNOWN" placed x (1, 0, 0) y (0, 1, 0) z (0, 0, 1) at (0, 0, 0)
component "Battery_L_INSTALLATION_ALLOWANCE_32x22x5p5_NOT_CELL" placed x (1, 0, 0) y (0, 1, 0) z (0, 0, 1) at (-66, -51, -9)
equation "outside_offset = 4 mm" comment "Provisional study, actual hardware/fit not verified"
equation "PCB_side_clearance = 1 mm" comment "Provisional study, actual hardware/fit not verified"
equation "floor_thickness = 2 mm" comment "Provisional study, actual hardware/fit not verified"
equation "lower_wall_height = 8.5 mm" comment "Provisional study, actual hardware/fit not verified"
equation "upper_frame_height = 5.5 mm" comment "Provisional study, actual hardware/fit not verified"
equation "stand_depth = 3.7 mm" comment "Provisional study, actual hardware/fit not verified"
equation "stand_residual = 2 mm" comment "Provisional study, actual hardware/fit not verified"
equation "support_height = 3.3 mm" comment "Provisional study, actual hardware/fit not verified"
equation "M2_clearance = 2.2 mm" comment "Provisional study, actual hardware/fit not verified"
equation "M2_tap_pilot = 1.6 mm" comment "Provisional study, actual hardware/fit not verified"
equation "M2_pilot_depth = 4.5 mm" comment "Provisional study, actual hardware/fit not verified"
equation "boss_diameter = 6 mm" comment "Provisional study, actual hardware/fit not verified"
equation "d13 = outside_offset"
equation "d14 = floor_thickness"
equation "d16 = floor_thickness"
equation "d18 = outside_offset"
equation "d19 = PCB_side_clearance"
equation "d20 = lower_wall_height"
equation "d22 = stand_depth + stand_residual - floor_thickness"
equation "d24 = stand_depth"
equation "d28 = support_height"
equation "d30 = support_height"
equation "d32 = support_height"
equation "d34 = support_height"
equation "d36 = outside_offset"
equation "d37 = PCB_side_clearance"
equation "d38 = upper_frame_height"
equation "d40 = floor_thickness + lower_wall_height"
equation "d42 = upper_frame_height"
equation "d44 = floor_thickness + lower_wall_height"
equation "d46 = M2_pilot_depth"
equation "head_seat_depth = 2.2 mm" comment "Provisional 2 mm high socket cap + 0.2 mm recess"
equation "d81 = head_seat_depth"
equation "head_seat_diameter = 4.2 mm" comment "Provisional socket head seat diameter"
equation "d84 = boss_diameter / 2"
equation "d85 = boss_diameter / 2"
equation "d86 = boss_diameter / 2"
equation "d87 = boss_diameter / 2"
equation "d88 = M2_tap_pilot / 2"
equation "d89 = M2_tap_pilot / 2"
equation "d90 = M2_tap_pilot / 2"
equation "d91 = M2_tap_pilot / 2"
equation "d92 = boss_diameter / 2"
equation "d93 = boss_diameter / 2"
equation "d94 = boss_diameter / 2"
equation "d95 = boss_diameter / 2"
equation "d96 = M2_clearance / 2"
equation "d97 = M2_clearance / 2"
equation "d98 = M2_clearance / 2"
equation "d99 = M2_clearance / 2"
equation "d100 = head_seat_diameter / 2"
equation "d101 = head_seat_diameter / 2"
equation "d102 = head_seat_diameter / 2"
equation "d103 = head_seat_diameter / 2"
